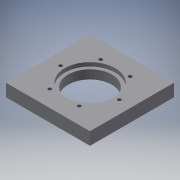
# Autodesk Inventor part: 15-0012-0324
Saved by Autodesk Inventor 2016 SP2 (Build 200236200, 236)
## iProperties
Created: 2017-10-30
Part Number: 15-0012-0324
Material: Generic
Document SubType Name: Modeling
Designer: jellerm1
Density: 0.001 g/cm^3
Appearance: Default
RuleStatus: InUse
BeforeDocSave0: Open Form
Author: jellerm1
Autodesk Inventor part; units mm, degrees
ref_plane "YZ Plane" through (0, 0, 0) normal (1, 0, 0) x (0, 1, 0)
ref_plane "XZ Plane" through (0, 0, 0) normal (0, 1, 0) x (-1, 0, 0)
ref_plane "XY Plane" through (0, 0, 0) normal (0, 0, 1) x (1, 0, 0)
sketch "Sketch1" plane through (0, 0, 0) normal (0, 0, 1) x (1, 0, 0)
  line L0 (0, 70) -> (0, -70) construction
  line L1 (-70, 0) -> (70, 0) construction
  line L2 (-50, -50) -> (50, -50)
  line L3 (50, -50) -> (50, 50)
  line L4 (50, 50) -> (-50, 50)
  line L5 (-50, 50) -> (-50, -50)
  line L6 (-50, -50) -> (50, 50) construction
  line L7 (50, -50) -> (-50, 50) construction
  circle A0 centre (0, 0) radius 30
  circle A1 centre (0, 0) radius 26
  point P0 (-35, 0)
  dimension "d0" = 100
  dimension "d1" = 100
  dimension "d2" = 60
  dimension "d3" = 52
  dimension "d8" = 35
  constraints: 12 end point, 2 centre point, 2 coincident, 2 midpoint, 2 parallel, 1 horizontal, 1 perpendicular, 1 point on line
  measures "d0" distance of L4.end L3.end
  measures "d1" distance of L3.end L2.end
  measures "d2" diameter of A0
  measures "d3" diameter of A1
  measures "d8" distance from line of L0 point (-35, 0)
extrude "Extrusion1" add sketch "Sketch1" against normal blind 15 contours L5 L4 L3 L2 | A0
extrude "Extrusion2" cut sketch "Sketch1" against normal blind 4.5 contours A0
hole "Hole1" at (-35, 0, 0) direction (0, 0, -1) diameter 4.134 depth 12 tip angle 118 thread size "M5x0.8" class "6H" standard "ISO Metric profile"
pattern_circular "Circular Pattern1" count 6 over 360 about axis through (0, 0, 0) along (0, 0, -1) of "Hole1"
body "Solid1"
